360002_P01_FRONT-FIXED-GLASS-UNIT_CAD (Autodesk Fusion 360 design; units mm, degrees)
description: FRONT - FIXED GLASS UNIT | Cụm vách kính cố định | P01
part number: 360002
description: FRONT - FIXED GLASS - 4+4 LAMINATED | Tấm kính cố định 4+4 | P01
part number: 361003
description: FRONT - GLAZING U-PROFILE - BOHLE BO5201571 | Thanh U nhôm kẹp kính | P01
part number: 368004
description: FRONT - GLAZING U-SEAL - BOHLE BO5201735 | Gioăng chữ U silicone | P01
part number: 368002
description: FRONT - 180 MAGNETIC SEAL - HALF 1 OF 2 - HOLD | Gioăng nam châm 180° phía vách (chờ chọn) | P01
part number: 368003
Autodesk Fusion 360 part; units mm, degrees
sketch "OUTLINE - FIXED GLASS (SKELETON PENTAGON + BITE ON 4 EDGES)" plane through (0, 0, 0) normal (0, 1, 0) x (1, 0, 0) in component "361003 FRONT - FIXED GLASS - 4+4 LAMINATED"
  line L0 (218.9506, -98.5) -> (960.1034, -98.5)
  line L1 (960.1034, -98.5) -> (759.9166, -1525.9624)
  line L2 (759.9166, -1525.9624) -> (235.2521, -2131.5)
  line L3 (235.2521, -2131.5) -> (-66.1344, -2131.5)
  line L4 (-66.1344, -2131.5) -> (218.9506, -98.5)
  point P0 (-5000, 5000)
  dimension "d1397" = 5000
  dimension "d1398" = 5000
  dimension "d1399" = 5218.9506
  dimension "d1400" = 5960.1034
  dimension "d1401" = 5759.9166
  dimension "d1402" = 5235.2521
  dimension "d1403" = 4933.8656
  dimension "d1405" = 6525.9624
  constraint horizontal L0
  constraint horizontal L3
  measures "d1397" horizontal distance of origin P0
  measures "d1398" vertical distance of origin P0
  measures "d1399" horizontal distance of L0.start P0
  measures "d1400" horizontal distance of L0.end P0
  measures "d1401" horizontal distance of L1.end P0
  measures "d1402" horizontal distance of L2.end P0
  measures "d1403" horizontal distance of L3.end P0
  measures "d1405" vertical distance of L1.end P0
extrude "EXTRUDE - FIXED GLASS 8.76" add sketch "OUTLINE - FIXED GLASS (SKELETON PENTAGON + BITE ON 4 EDGES)" along normal blind 8.76 from surface at -703.38 makes body 1 in component "361003 FRONT - FIXED GLASS - 4+4 LAMINATED"
sketch "BAND - U-PROFILE OUTER (4 EDGES, MITRED)" plane through (0, 0, 0) normal (0, 1, 0) x (1, 0, 0) in component "368004 FRONT - GLAZING U-PROFILE - BOHLE BO5201571"
  line L0 (217.338, -110) -> (946.8781, -110)
  line L1 (946.8781, -110) -> (749, -1521)
  line L2 (749, -1521) -> (230, -2120)
  line L3 (230, -2120) -> (-64.5218, -2120)
  line L4 (-64.5218, -2120) -> (-66.6252, -2135)
  line L5 (-66.6252, -2135) -> (236.8506, -2135)
  line L6 (236.8506, -2135) -> (763.2391, -1527.4726)
  line L7 (763.2391, -1527.4726) -> (964.1285, -95)
  line L8 (964.1285, -95) -> (219.4414, -95)
  line L9 (219.4414, -95) -> (217.338, -110)
  point P0 (-5000, 5000)
  dimension "d1410" = 5000
  dimension "d1411" = 5000
  dimension "d1412" = 5217.338
  dimension "d1413" = 5946.8781
  dimension "d1414" = 5749
  dimension "d1415" = 5230
  dimension "d1416" = 4935.4782
  dimension "d1417" = 4933.3748
  dimension "d1418" = 5236.8506
  dimension "d1419" = 5763.2391
  dimension "d1420" = 5964.1285
  dimension "d1421" = 5219.4414
  dimension "d1422" = 5110
  dimension "d1423" = 6521
  dimension "d1424" = 7120
  dimension "d1426" = 6527.4726
  constraint horizontal L0
  constraint horizontal L3
  constraint horizontal L5
  constraint horizontal L8
  measures "d1410" horizontal distance of origin P0
  measures "d1411" vertical distance of origin P0
  measures "d1412" horizontal distance of L0.start P0
  measures "d1413" horizontal distance of L0.end P0
  measures "d1414" horizontal distance of L1.end P0
  measures "d1415" horizontal distance of L2.end P0
  measures "d1416" horizontal distance of L3.end P0
  measures "d1417" horizontal distance of L4.end P0
  measures "d1418" horizontal distance of L5.end P0
  measures "d1419" horizontal distance of L6.end P0
  measures "d1420" horizontal distance of L7.end P0
  measures "d1421" horizontal distance of L8.end P0
  measures "d1422" vertical distance of L0.start P0
  measures "d1423" vertical distance of L1.end P0
  measures "d1424" vertical distance of L2.end P0
  measures "d1426" vertical distance of L6.end P0
extrude "EXTRUDE - U-PROFILE BAR" add sketch "BAND - U-PROFILE OUTER (4 EDGES, MITRED)" along normal blind 15 from surface at -706.5 separate body makes body 2 in component "368004 FRONT - GLAZING U-PROFILE - BOHLE BO5201571"
sketch "BAND - U-PROFILE CHANNEL" plane through (0, 0, 0) normal (0, 1, 0) x (1, 0, 0) in component "368004 FRONT - GLAZING U-PROFILE - BOHLE BO5201571"
  line L0 (217.338, -110) -> (946.8781, -110)
  line L1 (946.8781, -110) -> (749, -1521)
  line L2 (749, -1521) -> (230, -2120)
  line L3 (230, -2120) -> (-64.5218, -2120)
  line L4 (-64.5218, -2120) -> (-66.4149, -2133.5)
  line L5 (-66.4149, -2133.5) -> (236.1655, -2133.5)
  line L6 (236.1655, -2133.5) -> (761.8152, -1526.8254)
  line L7 (761.8152, -1526.8254) -> (962.4034, -96.5)
  line L8 (962.4034, -96.5) -> (219.2311, -96.5)
  line L9 (219.2311, -96.5) -> (217.338, -110)
  point P0 (-5000, 5000)
  dimension "d1431" = 5000
  dimension "d1432" = 5000
  dimension "d1433" = 5217.338
  dimension "d1434" = 5946.8781
  dimension "d1435" = 5749
  dimension "d1436" = 5230
  dimension "d1437" = 4935.4782
  dimension "d1438" = 4933.5851
  dimension "d1439" = 5236.1655
  dimension "d1440" = 5761.8152
  dimension "d1441" = 5962.4034
  dimension "d1442" = 5219.2311
  dimension "d1443" = 5110
  dimension "d1444" = 6521
  dimension "d1445" = 7120
  dimension "d1447" = 6526.8254
  constraint horizontal L0
  constraint horizontal L3
  constraint horizontal L5
  constraint horizontal L8
  measures "d1431" horizontal distance of origin P0
  measures "d1432" vertical distance of origin P0
  measures "d1433" horizontal distance of L0.start P0
  measures "d1434" horizontal distance of L0.end P0
  measures "d1435" horizontal distance of L1.end P0
  measures "d1436" horizontal distance of L2.end P0
  measures "d1437" horizontal distance of L3.end P0
  measures "d1438" horizontal distance of L4.end P0
  measures "d1439" horizontal distance of L5.end P0
  measures "d1440" horizontal distance of L6.end P0
  measures "d1441" horizontal distance of L7.end P0
  measures "d1442" horizontal distance of L8.end P0
  measures "d1443" vertical distance of L0.start P0
  measures "d1444" vertical distance of L1.end P0
  measures "d1445" vertical distance of L2.end P0
  measures "d1447" vertical distance of L6.end P0
extrude "CUT - U-PROFILE CHANNEL 12 X 13.5" cut sketch "BAND - U-PROFILE CHANNEL" along normal blind 12 from surface at -705 bodies 2 in component "368004 FRONT - GLAZING U-PROFILE - BOHLE BO5201571"
sketch "HOLES - BOTTOM CHANNEL SCREWS TO THE SILL (4)" plane through (0, 0, 0) normal (0, 0, 1) x (1, 0, 0) in component "368004 FRONT - GLAZING U-PROFILE - BOHLE BO5201571"
  circle A0 centre (269.4414, -699) radius 1.7
  circle A1 centre (484.3371, -699) radius 1.7
  circle A2 centre (699.2328, -699) radius 1.7
  circle A3 centre (905, -699) radius 1.7
  point P0 (-5000, -5000)
  dimension "d1452" = 5000
  dimension "d1453" = 5000
  dimension "d1454" = 5269.4414
  dimension "d1456" = 3.4
  dimension "d1457" = 5484.3371
  dimension "d1459" = 3.4
  dimension "d1460" = 5699.2328
  dimension "d1462" = 3.4
  dimension "d1463" = 5905
  dimension "d1465" = 3.4
  measures "d1452" horizontal distance of origin P0
  measures "d1453" vertical distance of origin P0
  measures "d1454" horizontal distance of P0 A0.centre
  measures "d1456" diameter of A0
  measures "d1457" horizontal distance of P0 A1.centre
  measures "d1459" diameter of A1
  measures "d1460" horizontal distance of P0 A2.centre
  measures "d1462" diameter of A2
  measures "d1463" horizontal distance of P0 A3.centre
  measures "d1465" diameter of A3
extrude "CUT - BOTTOM CHANNEL SCREW HOLES" cut sketch "HOLES - BOTTOM CHANNEL SCREWS TO THE SILL (4)" along normal blind 3.5 from surface at 94 bodies 2 in component "368004 FRONT - GLAZING U-PROFILE - BOHLE BO5201571"
sketch "BAND - U-SEAL OUTER" plane through (0, 0, 0) normal (0, 1, 0) x (1, 0, 0) in component "368002 FRONT - GLAZING U-SEAL - BOHLE BO5201735"
  line L0 (217.338, -110) -> (946.8781, -110)
  line L1 (946.8781, -110) -> (749, -1521)
  line L2 (749, -1521) -> (230, -2120)
  line L3 (230, -2120) -> (-64.5218, -2120)
  line L4 (-64.5218, -2120) -> (-66.4149, -2133.5)
  line L5 (-66.4149, -2133.5) -> (236.1655, -2133.5)
  line L6 (236.1655, -2133.5) -> (761.8152, -1526.8254)
  line L7 (761.8152, -1526.8254) -> (962.4034, -96.5)
  line L8 (962.4034, -96.5) -> (219.2311, -96.5)
  line L9 (219.2311, -96.5) -> (217.338, -110)
  point P0 (-5000, 5000)
  dimension "d1469" = 5000
  dimension "d1470" = 5000
  dimension "d1471" = 5217.338
  dimension "d1472" = 5946.8781
  dimension "d1473" = 5749
  dimension "d1474" = 5230
  dimension "d1475" = 4935.4782
  dimension "d1476" = 4933.5851
  dimension "d1477" = 5236.1655
  dimension "d1478" = 5761.8152
  dimension "d1479" = 5962.4034
  dimension "d1480" = 5219.2311
  dimension "d1481" = 5110
  dimension "d1482" = 6521
  dimension "d1483" = 7120
  dimension "d1485" = 6526.8254
  constraint horizontal L0
  constraint horizontal L3
  constraint horizontal L5
  constraint horizontal L8
  measures "d1469" horizontal distance of origin P0
  measures "d1470" vertical distance of origin P0
  measures "d1471" horizontal distance of L0.start P0
  measures "d1472" horizontal distance of L0.end P0
  measures "d1473" horizontal distance of L1.end P0
  measures "d1474" horizontal distance of L2.end P0
  measures "d1475" horizontal distance of L3.end P0
  measures "d1476" horizontal distance of L4.end P0
  measures "d1477" horizontal distance of L5.end P0
  measures "d1478" horizontal distance of L6.end P0
  measures "d1479" horizontal distance of L7.end P0
  measures "d1480" horizontal distance of L8.end P0
  measures "d1481" vertical distance of L0.start P0
  measures "d1482" vertical distance of L1.end P0
  measures "d1483" vertical distance of L2.end P0
  measures "d1485" vertical distance of L6.end P0
extrude "EXTRUDE - U-SEAL" add sketch "BAND - U-SEAL OUTER" along normal blind 12 from surface at -705 separate body makes body 3 in component "368002 FRONT - GLAZING U-SEAL - BOHLE BO5201735"
sketch "BAND - U-SEAL GLASS SLOT" plane through (0, 0, 0) normal (0, 1, 0) x (1, 0, 0) in component "368002 FRONT - GLAZING U-SEAL - BOHLE BO5201735"
  line L0 (217.338, -110) -> (946.8781, -110)
  line L1 (946.8781, -110) -> (749, -1521)
  line L2 (749, -1521) -> (230, -2120)
  line L3 (230, -2120) -> (-64.5218, -2120)
  line L4 (-64.5218, -2120) -> (-66.1344, -2131.5)
  line L5 (-66.1344, -2131.5) -> (235.2521, -2131.5)
  line L6 (235.2521, -2131.5) -> (759.9166, -1525.9624)
  line L7 (759.9166, -1525.9624) -> (960.1034, -98.5)
  line L8 (960.1034, -98.5) -> (218.9506, -98.5)
  line L9 (218.9506, -98.5) -> (217.338, -110)
  point P0 (-5000, 5000)
  dimension "d1490" = 5000
  dimension "d1491" = 5000
  dimension "d1492" = 5217.338
  dimension "d1493" = 5946.8781
  dimension "d1494" = 5749
  dimension "d1495" = 5230
  dimension "d1496" = 4935.4782
  dimension "d1497" = 4933.8656
  dimension "d1498" = 5235.2521
  dimension "d1499" = 5759.9166
  dimension "d1500" = 5960.1034
  dimension "d1501" = 5218.9506
  dimension "d1502" = 5110
  dimension "d1503" = 6521
  dimension "d1504" = 7120
  dimension "d1506" = 6525.9624
  constraint horizontal L0
  constraint horizontal L3
  constraint horizontal L5
  constraint horizontal L8
  measures "d1490" horizontal distance of origin P0
  measures "d1491" vertical distance of origin P0
  measures "d1492" horizontal distance of L0.start P0
  measures "d1493" horizontal distance of L0.end P0
  measures "d1494" horizontal distance of L1.end P0
  measures "d1495" horizontal distance of L2.end P0
  measures "d1496" horizontal distance of L3.end P0
  measures "d1497" horizontal distance of L4.end P0
  measures "d1498" horizontal distance of L5.end P0
  measures "d1499" horizontal distance of L6.end P0
  measures "d1500" horizontal distance of L7.end P0
  measures "d1501" horizontal distance of L8.end P0
  measures "d1502" vertical distance of L0.start P0
  measures "d1503" vertical distance of L1.end P0
  measures "d1504" vertical distance of L2.end P0
  measures "d1506" vertical distance of L6.end P0
extrude "CUT - U-SEAL GLASS SLOT" cut sketch "BAND - U-SEAL GLASS SLOT" along normal blind 8.76 from surface at -703.38 bodies 3 in component "368002 FRONT - GLAZING U-SEAL - BOHLE BO5201735"
sketch "OUTLINE - 180 SEAL SPACE ON THE FREE EDGE" plane through (0, 0, 0) normal (0, 1, 0) x (1, 0, 0) in component "368003 FRONT - 180 MAGNETIC SEAL - HALF 1 OF 2 - HOLD"
  line L0 (217.338, -110) -> (-64.5218, -2120)
  line L1 (-64.5218, -2120) -> (-66.5413, -2120)
  line L2 (-66.5413, -2120) -> (215.3184, -110)
  line L3 (215.3184, -110) -> (217.338, -110)
  point P0 (-5000, 5000)
  dimension "d1511" = 5000
  dimension "d1512" = 5000
  dimension "d1513" = 5217.338
  dimension "d1514" = 4935.4782
  dimension "d1515" = 4933.4587
  dimension "d1516" = 5215.3184
  dimension "d1517" = 7120
  dimension "d1518" = 5110
  constraint horizontal L1
  constraint horizontal L3
  measures "d1511" horizontal distance of origin P0
  measures "d1512" vertical distance of origin P0
  measures "d1513" horizontal distance of L0.start P0
  measures "d1514" horizontal distance of L0.end P0
  measures "d1515" horizontal distance of L1.end P0
  measures "d1516" horizontal distance of L2.end P0
  measures "d1517" vertical distance of L0.end P0
  measures "d1518" vertical distance of L2.end P0
extrude "EXTRUDE - 180 SEAL SPACE" add sketch "OUTLINE - 180 SEAL SPACE ON THE FREE EDGE" along normal blind 11.76 from surface at -704.88 separate body makes body 4 in component "368003 FRONT - 180 MAGNETIC SEAL - HALF 1 OF 2 - HOLD"
component "361003 FRONT - FIXED GLASS - 4+4 LAMINATED" placed x (1, 0, 0) y (0, 1, 0) z (0, 0, 1) at (0, 0, 0)
component "368004 FRONT - GLAZING U-PROFILE - BOHLE BO5201571" placed x (1, 0, 0) y (0, 1, 0) z (0, 0, 1) at (0, 0, 0)
component "368002 FRONT - GLAZING U-SEAL - BOHLE BO5201735" placed x (1, 0, 0) y (0, 1, 0) z (0, 0, 1) at (0, 0, 0)
component "368003 FRONT - 180 MAGNETIC SEAL - HALF 1 OF 2 - HOLD" placed x (1, 0, 0) y (0, 1, 0) z (0, 0, 1) at (0, 0, 0)
equation "pod_w = 2500 mm" comment "SKELETON P04 DECIDED: D-01; conventions s4 (X = +-1250)"
equation "pod_d = 1700 mm" comment "SKELETON P04 DECIDED: D-01; conventions s4 (Y = +-850)"
equation "pod_h = 2400 mm" comment "SKELETON P04 DECIDED: D-21 (room floor to roof skin top)"
equation "glide_h = 10 mm" comment "SKELETON P04 ASSUMPTION: layout study inputs.py glide_h"
equation "band_h = 100 mm" comment "SKELETON P04 SOURCE: layout study B1 list B-BAND 100x40; inputs.py base_h"
equation "band_t = 40 mm" comment "SKELETON P04 SOURCE: layout study B1 list B-BAND 100x40"
equation "skin_t = 3 mm" comment "SKELETON P04 DECIDED: ACP skin, walls and ceiling (D-16; PM ruling 2026-10-31 on outer_t)"
equation "bond_t = 3 mm" comment "SKELETON P04 DECIDED: bond line between the ACP and the frame (PM ruling 2026-10-31 on outer_t)"
equation "frame_t = 40 mm" comment "SKELETON P04 DECIDED: aluminium frame tube depth, walls and ceiling (PM ruling 2026-10-31 on outer_t)"
equation "outer_t = skin_t + bond_t + frame_t" comment "SKELETON P04 DECIDED: PM ruling 2026-10-31: ACP 3 + bond line 3 + frame 40, walls and ceiling (was 43)"
equation "cav_gap = 4 mm" comment "SKELETON P04 DECIDED: D-16, D-42: the gap between the outer panel and the lining cassette in the wall and ceiling stack"
equation "cass_t = 34 mm" comment "SKELETON P04 SOURCE: layout study B1 final list L-CASS 34 (tray + 25 gap + felt 9)"
equation "stack_t = outer_t + cav_gap + cass_t" comment "SKELETON P04 CALCULATION: D-16, D-42 stack, walls and ceiling: outer panel + cavity gap + cassette (PM ruling 2026-10-31 on outer_t)"
equation "wall_depth = 1495 mm" comment "SKELETON P04 DECIDED: PM ruling pass C: side walls start at the decor back plate (Y -645), as v1 (1496)"
equation "lin_gap = 4 mm" comment "SKELETON P04 ASSUMPTION: PM ruling pass C: gap above the upper side linings so they stay floating (= the 4 mm stack gap)"
equation "seam_gap = 2.26 mm" comment "SKELETON P04 DECIDED: PM ruling 2026-10-31 (Mechanical Checker F-001, F-005): the Joints Engineer's 2.26 mm at all nine site seam types, set by a metal stop (1.5 stop washer + 0.76 rivnut head; joints register section 2.8)"
equation "mat_t = 3 mm" comment "SKELETON P04 DECIDED: D-72, PM ruling 2026-10-31 (from BASE): the 3 mm floor mat under the floor ply"
equation "floor_t = 9 mm" comment "SKELETON P04 DECIDED: PM ruling 2026-10-31: 9 mm floor panels (was 15, layout study B1 list), on the mat"
equation "thresh_h = 13 mm" comment "SKELETON P04 DECIDED: PM ruling 2026-10-31: 13 mm, a US-accessible threshold (D-18 had 20); the kick strip keeps its kick_gap above it"
equation "thresh_d = 60 mm" comment "SKELETON P04 SOURCE: layout study B1 list B-THRESH 1176 x 60 x 20"
equation "decor_d = 205 mm" comment "SKELETON P04 SOURCE: v1 geometry per the PM ruling on D-39 (as v1; the drawings win): v1 decor-frame drawing frames 191 (left) and 197 (right) deep plus ACP and back plate = the v1 STEP shell, Y -850 to -645 = 205. D-39 and the B1 list say 230-235 (v1 BOM); see BUILD-RECORD-P02"
equation "dl_w = 278 mm" comment "SKELETON P04 SOURCE: B1 list F-DL 278 (v1 BOM DL)"
equation "dr_w = 1016 mm" comment "SKELETON P04 SOURCE: B1 list F-DR 1016 (v1 STEP solid 78)"
equation "dt_w = 1697 mm" comment "SKELETON P04 SOURCE: B1 list F-DT 1697 (v1 BOM DT)"
equation "dt_h = 280 mm" comment "SKELETON P04 SOURCE: B1 list F-DT 280"
equation "door_w = 1176 mm" comment "SKELETON P04 DECIDED: D-46"
equation "door_h = 2011 mm" comment "SKELETON P04 SOURCE: B1 list F-GLASS-DOOR 2011; v1 STEP solid 238"
equation "glass_t = 8.76 mm" comment "SKELETON P04 DECIDED: D-46 (4+4 laminate)"
equation "glass_y = 699 mm" comment "SKELETON P04 SOURCE: v1 STEP solid 238 centre Y = -699 (layout study data)"
equation "kick_d = 20 mm" comment "SKELETON P04 ASSUMPTION: kick strip envelope depth (D-40 gives the height only)"
equation "kick_gap = 7 mm" comment "SKELETON P04 SOURCE: FRONT door unit: 7 mm running gap between the threshold and the kick strip for the drop seal (Mechanical Checker F-002 on P03)"
equation "fr_dz = 17 mm" comment "SKELETON P04 CALCULATION: v1 front top 2417 (v2 frame) - pod_h 2400"
equation "door_xl = 289 mm" comment "SKELETON P04 SOURCE: V1-FRONT-FACETS: door left edge X -961 = -1250 + 289"
equation "door_xbr = 1464 mm" comment "SKELETON P04 SOURCE: V1-FRONT-FACETS: door bottom-right X 214"
equation "door_xtr = 1182 mm" comment "SKELETON P04 SOURCE: V1-FRONT-FACETS: door top-right X -68"
equation "door_zb = 122 mm - fr_dz" comment "SKELETON P04 SOURCE: V1-FRONT-FACETS: door bottom Z 122"
equation "door_zt = 2133 mm - fr_dz" comment "SKELETON P04 SOURCE: V1-FRONT-FACETS: door top Z 2133"
equation "glass_gap = 4 mm" comment "SKELETON P04 DECIDED: PM ruling 2026-10-31 on Mechanical Checker F-014: the fixed glass's free edge runs parallel to the door's slanted edge, 4.0 mm away (FRONT's glass in PR #28 is the reference)"
equation "fix_xbr = 302 mm" comment "SKELETON P04 SOURCE: V1-FRONT-FACETS: fixed glass bottom-right X 948 = 1250 - 302"
equation "fix_xk = 501 mm" comment "SKELETON P04 SOURCE: V1-FRONT-FACETS: fixed glass knee X 749 = 1250 - 501"
equation "fix_zk = 1538 mm - fr_dz" comment "SKELETON P04 SOURCE: V1-FRONT-FACETS: fixed glass knee Z 1538"
equation "fix_xtr = 1480 mm" comment "SKELETON P04 SOURCE: V1-FRONT-FACETS: fixed glass top-right X 230 = -1250 + 1480"
equation "fix_zb = 119 mm - fr_dz" comment "SKELETON P04 SOURCE: V1-FRONT-FACETS: fixed glass bottom Z 119"
equation "fix_zt = 2136 mm - fr_dz" comment "SKELETON P04 SOURCE: V1-FRONT-FACETS: fixed glass top Z 2136"
equation "dt_zb = 2137 mm - fr_dz" comment "SKELETON P04 SOURCE: V1-FRONT-FACETS: DT and DR edge above the glass Z 2137"
equation "ch_zlo = 2217 mm - fr_dz" comment "SKELETON P04 SOURCE: V1-FRONT-FACETS: top chamfer front edge Z 2217 at Y -848"
equation "ch_yb = 672 mm" comment "SKELETON P04 SOURCE: V1-FRONT-FACETS: top chamfer back edge Y -672"
equation "dl_x2 = 92 mm" comment "SKELETON P04 SOURCE: V1-FRONT-FACETS: DL facet knee X -1158 = -1250 + 92"
equation "dl_y2 = 752 mm" comment "SKELETON P04 SOURCE: V1-FRONT-FACETS: DL facet knee Y -752"
equation "dl_x3 = 271 mm" comment "SKELETON P04 SOURCE: V1-FRONT-FACETS: DL front corner X -979"
equation "dl_y3 = 844 mm" comment "SKELETON P04 SOURCE: V1-FRONT-FACETS: DL front corner Y -844"
equation "dl_y1 = 670 mm" comment "SKELETON P04 SOURCE: V1-FRONT-FACETS: DL outer facet start Y -670"
equation "dl_zo = 2414 mm - fr_dz" comment "SKELETON P04 SOURCE: V1-FRONT-FACETS: DL top at the outer corner Z 2414"
equation "dt_x2 = 281 mm" comment "SKELETON P04 SOURCE: V1-FRONT-FACETS: DT lower facet left X -969 = -1250 + 281"
equation "dt_y2 = 767 mm" comment "SKELETON P04 SOURCE: V1-FRONT-FACETS: DT lower facet left Y -767"
equation "dt_y3 = 753 mm" comment "SKELETON P04 SOURCE: V1-FRONT-FACETS: DT lower facet outer Y -753 at X -1154"
equation "dr_xc = 198 mm" comment "SKELETON P04 SOURCE: V1-FRONT-FACETS: DR corner facet front X 1052 = 1250 - 198"
equation "dt_xr = 1699 mm" comment "SKELETON P04 SOURCE: V1-FRONT-FACETS: DT/DR joint at the top, X 449 = -1250 + 1699 (PM ruling pass C)"
equation "dr_yc = 672 mm" comment "SKELETON P04 SOURCE: V1-FRONT-FACETS: DR corner facet back Y -672"
equation "fix_xbl = door_xbr + ( door_zb - fix_zb ) * ( door_xbr - door_xtr ) / ( door_zt - door_zb ) + glass_gap * sqrt(( door_xbr - door_xtr ) * ( door_xbr - door_xtr ) + ( door_zt - door_zb ) * ( door_zt - door_zb )) / ( door_zt - door_zb )" comment "SKELETON P04 CALCULATION: F-014: fixed glass bottom-left, on the line glass_gap from the door's slanted edge (was v1's 1468)"
equation "fix_xtl = door_xbr + ( door_zb - fix_zt ) * ( door_xbr - door_xtr ) / ( door_zt - door_zb ) + glass_gap * sqrt(( door_xbr - door_xtr ) * ( door_xbr - door_xtr ) + ( door_zt - door_zb ) * ( door_zt - door_zb )) / ( door_zt - door_zb )" comment "SKELETON P04 CALCULATION: F-014: fixed glass top-left, on the same line (was v1's 1184)"
equation "floor_top = mat_t + floor_t" comment "SKELETON P04 CALCULATION: D-72: the floor top, Z 12 (mat 3 + ply 9); the threshold stands thresh_h above the room floor"
equation "wall_z0 = glide_h + band_h" comment "SKELETON P04 CALCULATION: base band top: glides + band"
equation "panel_z0 = wall_z0 + seam_gap" comment "SKELETON P04 CALCULATION: walls stand one seam_gap above the band top (joints register 2.8, IF-01)"
equation "wall_h = pod_h - wall_z0" comment "SKELETON P04 CALCULATION: 2290 = layout study v2_model wall_h"
equation "side_h = ( wall_h - 2 * seam_gap ) / 2" comment "SKELETON P04 CALCULATION: D-23: 2 sheets per side wall; the gap on the band and the horizontal seam (joints register 2.8)"
equation "side_l = wall_depth - seam_gap" comment "SKELETON P04 CALCULATION: side panel length along Y: the seam_gap at the decor's back plate (joints register 2.8, IF-07)"
equation "back_oh = pod_h - outer_t - seam_gap - panel_z0" comment "SKELETON P04 CALCULATION: PM ruling 2026-10-31 (pass D, F-004): the back outer frames run up to the ceiling frame (pod_h - outer_t), less the seam_gap under it, closing the slot at the back top edge"
equation "back_ph = ( back_oh - seam_gap ) / 2" comment "SKELETON P04 CALCULATION: D-23: 4 sheets on the back, two equal rows with one seam_gap between them (joints register 2.8); the lower back linings match the lower row, as on the side walls"
equation "half_pw = ( pod_w - 2 * outer_t - 3 * seam_gap ) / 2" comment "SKELETON P04 CALCULATION: SKIN width of each back and ceiling panel: two skins and three seam_gap seams between the side frames (F-001, joints register 2.8)"
equation "close_gap = 5.5 mm" comment "SKELETON P04 DECIDED: PM ruling 2026-10-31 (joints register, F-011/F-012): frame gap at the closing seams B1-B2, B3-B4 and C1-C2, which have no hard stop (slotted holes, thicker gasket)"
equation "half_fw = ( pod_w - 2 * outer_t - 2 * seam_gap - close_gap ) / 2" comment "SKELETON P04 CALCULATION: FRAME width of each back and ceiling panel: the skins overhang their frames by half_pw - half_fw at the closing seam (PM ruling 2026-10-31)"
equation "inner_w = pod_w - 2 * stack_t" comment "SKELETON P04 CALCULATION: inside width between the side linings"
equation "bolt_edge_inset = 220 mm" comment "SKELETON P04 DECIDED: PM ruling 2026-10-31: on every bolted edge the end bolts sit this far in from each panel end (the FRAME end, where the bolts go), the rest evenly spaced"
equation "spigot_inset = 100 mm" comment "SKELETON P04 DECIDED: PM ruling 2026-10-31: locating spigots this far in from each panel end (round hole at one end, slot at the other)"
equation "base_bolt_edge = bolt_edge_inset" comment "SKELETON P04 DECIDED: J-BASE-01 wall to band: the edge rule (kept by this name for parts already linked)"
equation "n_base_bolt = 4" comment "SKELETON P04 DECIDED: PM ruling 2026-10-31, J-BASE-01: bolts per panel along the band, evenly spaced"
equation "base_spigot_inset = spigot_inset" comment "SKELETON P04 DECIDED: J-BASE-01: the spigot rule (kept by this name for parts already linked)"
equation "base_side_y0 = pod_d / 2 - wall_depth + seam_gap" comment "SKELETON P04 CALCULATION: J-BASE-01: side bolt lines start at the side panel's front end (first bolt base_bolt_edge further on)"
equation "side_base_pitch = ( side_l - 2 * base_bolt_edge ) / ( n_base_bolt - 1 )" comment "SKELETON P04 CALCULATION: J-BASE-01 bolt pitch along a side panel"
equation "base_back_x0 = pod_w / 2 - outer_t - seam_gap" comment "SKELETON P04 CALCULATION: J-BASE-01: back bolt lines start at each back FRAME's outer end, X -/+ this (first bolt base_bolt_edge further in)"
equation "back_base_pitch = ( half_fw - 2 * base_bolt_edge ) / ( n_base_bolt - 1 )" comment "SKELETON P04 DECIDED: PM ruling 2026-10-31 (Reviewer 5 P2 on #58): J-BASE-01 pitch along a back panel, measured on the FRAME (half_fw), where the bolts go; 'panel end' means the frame end"
equation "ceil_bolt_z = pod_h - outer_t + frame_t / 2" comment "SKELETON P04 DECIDED: PM ruling 2026-10-31, J-CEIL-01 wall to ceiling: the bolt line on the ceiling frame's centre (Z 2374)"
equation "n_ceil_side_bolt = 4" comment "SKELETON P04 DECIDED: PM ruling 2026-10-31, J-CEIL-01: bolts along each side wall top"
equation "n_ceil_back_bolt = 4" comment "SKELETON P04 DECIDED: PM ruling 2026-10-31, J-CEIL-01: bolts along each back panel top, like the base (pitch about 253, every edge 350 or less; joints register: 82 bolts in all)"
equation "ceil_side_y0 = pod_d / 2 - wall_depth" comment "SKELETON P04 DECIDED: PM ruling 2026-10-31 (joints register): J-CEIL-01 side bolt lines start at Y -645, measured along the ceiling (first bolt bolt_edge_inset further on)"
equation "ceil_side_pitch = ( wall_depth - 2 * bolt_edge_inset ) / ( n_ceil_side_bolt - 1 )" comment "SKELETON P04 DECIDED: PM ruling 2026-10-31 (joints register): J-CEIL-01 pitch along a side wall top, over the ceiling's length (was over the side panel's)"
equation "ceil_back_x0 = pod_w / 2 - outer_t - seam_gap" comment "SKELETON P04 DECIDED: PM ruling 2026-10-31 (joints register): J-CEIL-01 back bolt lines start at each back frame's outer end, X -/+ this"
equation "ceil_back_pitch = ( half_fw - 2 * bolt_edge_inset ) / ( n_ceil_back_bolt - 1 )" comment "SKELETON P04 DECIDED: PM ruling 2026-10-31 (joints register): J-CEIL-01 pitch along a back panel top, on the frame (half_fw)"
equation "sk_ref = 5000 mm" comment "ASSUMPTION: sketch reference point offset: every sketch corner is dimensioned from a point at -sk_ref on both plane axes, so no dimension changes side when a corner crosses a pod centre line in an edit"
equation "fg_vis_zb = wall_z0" comment "CALCULATION: visible bottom of the fixed pane = the base band top (DL and DR stop there too, PM ruling 2026-10-31)"
equation "fg_vis_zt = dt_zb" comment "CALCULATION: visible top of the fixed pane = DT's underside"
equation "fg_gap = glass_gap" comment "CALCULATION: = the skeleton's glass_gap: the pane's free edge runs parallel to the door's latch edge, 4 mm off (PM ruling 2026-10-31; the skeleton's fix_xbl and fix_xtl follow the same rule since its update #58)"
equation "gu_prof_w = 15 mm" comment "SOURCE: Bohle BO5201571 aluminium U-profile 15 x 15 x 1.5 (hardware selection C5)"
equation "gu_prof_d = 15 mm" comment "SOURCE: as gu_prof_w"
equation "gu_prof_t = 1.5 mm" comment "SOURCE: as gu_prof_w"
equation "gu_w = gu_prof_w - 2 * gu_prof_t" comment "CALCULATION: inner width of the U-profile = the U-seal's outer width"
equation "gu_base = 2 mm" comment "ASSUMPTION: U-seal base under the glass edge; HOLD for Bohle's BO5201735 section drawing"
equation "gu_in_d = gu_prof_d - gu_prof_t" comment "CALCULATION: inner depth of the U-profile"
equation "fg_bite = gu_in_d - gu_base" comment "CALCULATION: glass cover in the hidden channels, 11.5 (PM ruling 2026-10-31); HOLD for the glass supplier's minimum"
equation "fg_r_len = sqrt(( fix_xbr - fix_xk ) * ( fix_xbr - fix_xk ) + ( fix_zk - fix_zb ) * ( fix_zk - fix_zb ))" comment "CALCULATION: length of the skeleton's right edge (bottom-right corner to the knee)"
equation "fg_rnx = ( fix_zk - fix_zb ) / fg_r_len" comment "CALCULATION: right edge outward normal, X"
equation "fg_rnz = ( fix_xk - fix_xbr ) / fg_r_len" comment "CALCULATION: right edge outward normal, Z"
equation "fg_rc = fg_rnx * ( pod_w / 2 - fix_xbr ) + fg_rnz * fix_zb" comment "CALCULATION: right edge line constant"
equation "fg_d_len = sqrt(( pod_w - fix_xtr - fix_xk ) * ( pod_w - fix_xtr - fix_xk ) + ( dt_zb - fix_zk ) * ( dt_zb - fix_zk ))" comment "CALCULATION: length of DR's diagonal inner edge (knee to DT's underside at X -pod_w/2 + fix_xtr)"
equation "fg_dnx = ( dt_zb - fix_zk ) / fg_d_len" comment "CALCULATION: diagonal outward normal, X"
equation "fg_dnz = ( pod_w - fix_xtr - fix_xk ) / fg_d_len" comment "CALCULATION: diagonal outward normal, Z"
equation "fg_dc = fg_dnx * ( pod_w / 2 - fix_xk ) + fg_dnz * fix_zk" comment "CALCULATION: diagonal line constant"
equation "fg_det = fg_rnx * fg_dnz - fg_rnz * fg_dnx" comment "CALCULATION: for the knee corner"
equation "fg_l_len = sqrt(( door_xbr - door_xtr ) * ( door_xbr - door_xtr ) + ( door_zt - door_zb ) * ( door_zt - door_zb ))" comment "CALCULATION: length of the door's latch edge"
equation "fg_lnx = ( door_zt - door_zb ) / fg_l_len" comment "CALCULATION: door latch edge normal toward the pane, X"
equation "fg_lnz = ( door_xbr - door_xtr ) / fg_l_len" comment "CALCULATION: door latch edge normal toward the pane, Z"
equation "fg_lc = fg_lnx * ( -pod_w / 2 + door_xbr ) + fg_lnz * door_zb" comment "CALCULATION: door latch edge line constant"
equation "gs_end = 50 mm" comment "SOURCE: PM ruling 2026-11-01 (BASE's sill): channel screws 50 from each end"
equation "gs_hole = 3.4 mm" comment "SOURCE: ISO 273 medium clearance hole for M3 (screw ISO 10642 M3 x 8, A2)"
equation "gs_csk = 7 mm" comment "CALCULATION: 90 deg countersink on the channel's inside face, over the ISO 10642 M3 head (6.72 max); the head stands about 0.4 proud of the 1.5 base and the U-seal's base covers it"
equation "gs_xl = ( ( fg_lc + fg_gap - fg_lnz * ( ( fg_vis_zb - gu_prof_d ) ) ) / fg_lnx )" comment "CALCULATION: left end of the bottom channel's underside (the pane's free edge)"
equation "gs_xr = ( ( fg_rc + gu_prof_d - fg_rnz * ( ( fg_vis_zb - gu_prof_d ) ) ) / fg_rnx )" comment "CALCULATION: right end of the bottom channel's underside, where it is mitred into the right-edge channel"
equation "base_fr1_x = 915 mm" comment "SOURCE: joints register (#127): BASE's front band inline joint FR1 at X 915; no sill rivnut on it (PM ruling 2026-11-01)"
equation "gs_x4 = base_fr1_x - 10 mm" comment "CONFIRMED: the last channel screw at X 905, clear of FR1's end; BASE moved the sill's last rivnut to match and kept the first three (PM ruling 2026-11-01); 59 from the channel's right end"
equation "gs_p = ( gs_xr - gs_xl - 2 * gs_end ) / 3" comment "CALCULATION: pitch of the first 3 channel screws (X 269.4, 484.3, 699.2, as BASE's sill rivnuts); 300 or less (PM ruling)"
equation "d1397 = sk_ref"
equation "d1398 = sk_ref"
equation "d1399 = ( ( ( fg_lc + fg_gap - fg_lnz * ( ( fg_vis_zb - fg_bite ) ) ) / fg_lnx ) ) + sk_ref"
equation "d1400 = ( ( ( fg_rc + fg_bite - fg_rnz * ( ( fg_vis_zb - fg_bite ) ) ) / fg_rnx ) ) + sk_ref"
equation "d1401 = ( ( ( ( fg_rc + fg_bite ) * fg_dnz - ( fg_dc + fg_bite ) * fg_rnz ) / fg_det ) ) + sk_ref"
equation "d1402 = ( ( ( fg_dc + fg_bite - fg_dnz * ( ( fg_vis_zt + fg_bite ) ) ) / fg_dnx ) ) + sk_ref"
equation "d1403 = ( ( ( fg_lc + fg_gap - fg_lnz * ( ( fg_vis_zt + fg_bite ) ) ) / fg_lnx ) ) + sk_ref"
equation "d1404 = ( ( fg_vis_zb - fg_bite ) ) + sk_ref"
equation "d1405 = ( ( ( fg_rnx * ( fg_dc + fg_bite ) - fg_dnx * ( fg_rc + fg_bite ) ) / fg_det ) ) + sk_ref"
equation "d1406 = ( ( fg_vis_zt + fg_bite ) ) + sk_ref"
equation "d1407 = ( -glass_y - glass_t / 2 ) * ( 1 )"
equation "d1408 = ( -glass_y + glass_t / 2 ) - ( -glass_y - glass_t / 2 )"
equation "d1410 = sk_ref"
equation "d1411 = sk_ref"
equation "d1412 = ( ( ( fg_lc + fg_gap - fg_lnz * ( ( fg_vis_zb - 0 mm ) ) ) / fg_lnx ) ) + sk_ref"
equation "d1413 = ( ( ( fg_rc + 0 mm - fg_rnz * ( ( fg_vis_zb - 0 mm ) ) ) / fg_rnx ) ) + sk_ref"
equation "d1414 = ( ( ( ( fg_rc + 0 mm ) * fg_dnz - ( fg_dc + 0 mm ) * fg_rnz ) / fg_det ) ) + sk_ref"
equation "d1415 = ( ( ( fg_dc + 0 mm - fg_dnz * ( ( fg_vis_zt + 0 mm ) ) ) / fg_dnx ) ) + sk_ref"
equation "d1416 = ( ( ( fg_lc + fg_gap - fg_lnz * ( ( fg_vis_zt + 0 mm ) ) ) / fg_lnx ) ) + sk_ref"
equation "d1417 = ( ( ( fg_lc + fg_gap - fg_lnz * ( ( fg_vis_zt + gu_prof_d ) ) ) / fg_lnx ) ) + sk_ref"
equation "d1418 = ( ( ( fg_dc + gu_prof_d - fg_dnz * ( ( fg_vis_zt + gu_prof_d ) ) ) / fg_dnx ) ) + sk_ref"
equation "d1419 = ( ( ( ( fg_rc + gu_prof_d ) * fg_dnz - ( fg_dc + gu_prof_d ) * fg_rnz ) / fg_det ) ) + sk_ref"
equation "d1420 = ( ( ( fg_rc + gu_prof_d - fg_rnz * ( ( fg_vis_zb - gu_prof_d ) ) ) / fg_rnx ) ) + sk_ref"
equation "d1421 = ( ( ( fg_lc + fg_gap - fg_lnz * ( ( fg_vis_zb - gu_prof_d ) ) ) / fg_lnx ) ) + sk_ref"
equation "d1422 = ( ( fg_vis_zb - 0 mm ) ) + sk_ref"
equation "d1423 = ( ( ( fg_rnx * ( fg_dc + 0 mm ) - fg_dnx * ( fg_rc + 0 mm ) ) / fg_det ) ) + sk_ref"
equation "d1424 = ( ( fg_vis_zt + 0 mm ) ) + sk_ref"
equation "d1425 = ( ( fg_vis_zt + gu_prof_d ) ) + sk_ref"
equation "d1426 = ( ( ( fg_rnx * ( fg_dc + gu_prof_d ) - fg_dnx * ( fg_rc + gu_prof_d ) ) / fg_det ) ) + sk_ref"
equation "d1427 = ( ( fg_vis_zb - gu_prof_d ) ) + sk_ref"
equation "d1428 = ( -glass_y - gu_prof_w / 2 ) * ( 1 )"
equation "d1429 = ( -glass_y + gu_prof_w / 2 ) - ( -glass_y - gu_prof_w / 2 )"
equation "d1431 = sk_ref"
equation "d1432 = sk_ref"
equation "d1433 = ( ( ( fg_lc + fg_gap - fg_lnz * ( ( fg_vis_zb - 0 mm ) ) ) / fg_lnx ) ) + sk_ref"
equation "d1434 = ( ( ( fg_rc + 0 mm - fg_rnz * ( ( fg_vis_zb - 0 mm ) ) ) / fg_rnx ) ) + sk_ref"
equation "d1435 = ( ( ( ( fg_rc + 0 mm ) * fg_dnz - ( fg_dc + 0 mm ) * fg_rnz ) / fg_det ) ) + sk_ref"
equation "d1436 = ( ( ( fg_dc + 0 mm - fg_dnz * ( ( fg_vis_zt + 0 mm ) ) ) / fg_dnx ) ) + sk_ref"
equation "d1437 = ( ( ( fg_lc + fg_gap - fg_lnz * ( ( fg_vis_zt + 0 mm ) ) ) / fg_lnx ) ) + sk_ref"
equation "d1438 = ( ( ( fg_lc + fg_gap - fg_lnz * ( ( fg_vis_zt + gu_in_d ) ) ) / fg_lnx ) ) + sk_ref"
equation "d1439 = ( ( ( fg_dc + gu_in_d - fg_dnz * ( ( fg_vis_zt + gu_in_d ) ) ) / fg_dnx ) ) + sk_ref"
equation "d1440 = ( ( ( ( fg_rc + gu_in_d ) * fg_dnz - ( fg_dc + gu_in_d ) * fg_rnz ) / fg_det ) ) + sk_ref"
equation "d1441 = ( ( ( fg_rc + gu_in_d - fg_rnz * ( ( fg_vis_zb - gu_in_d ) ) ) / fg_rnx ) ) + sk_ref"
equation "d1442 = ( ( ( fg_lc + fg_gap - fg_lnz * ( ( fg_vis_zb - gu_in_d ) ) ) / fg_lnx ) ) + sk_ref"
equation "d1443 = ( ( fg_vis_zb - 0 mm ) ) + sk_ref"
equation "d1444 = ( ( ( fg_rnx * ( fg_dc + 0 mm ) - fg_dnx * ( fg_rc + 0 mm ) ) / fg_det ) ) + sk_ref"
equation "d1445 = ( ( fg_vis_zt + 0 mm ) ) + sk_ref"
equation "d1446 = ( ( fg_vis_zt + gu_in_d ) ) + sk_ref"
equation "d1447 = ( ( ( fg_rnx * ( fg_dc + gu_in_d ) - fg_dnx * ( fg_rc + gu_in_d ) ) / fg_det ) ) + sk_ref"
equation "d1448 = ( ( fg_vis_zb - gu_in_d ) ) + sk_ref"
equation "d1449 = ( -glass_y - gu_w / 2 ) * ( 1 )"
equation "d1450 = ( -glass_y + gu_w / 2 ) - ( -glass_y - gu_w / 2 )"
equation "d1452 = sk_ref"
equation "d1453 = sk_ref"
equation "d1454 = ( gs_xl + gs_end + 0 * gs_p ) + sk_ref"
equation "d1455 = ( -glass_y ) + sk_ref"
equation "d1456 = gs_hole"
equation "d1457 = ( gs_xl + gs_end + 1 * gs_p ) + sk_ref"
equation "d1458 = ( -glass_y ) + sk_ref"
equation "d1459 = gs_hole"
equation "d1460 = ( gs_xl + gs_end + 2 * gs_p ) + sk_ref"
equation "d1461 = ( -glass_y ) + sk_ref"
equation "d1462 = gs_hole"
equation "d1463 = ( gs_x4 ) + sk_ref"
equation "d1464 = ( -glass_y ) + sk_ref"
equation "d1465 = gs_hole"
equation "d1466 = ( ( fg_vis_zb - gu_prof_d ) - 1 mm ) * ( 1 )"
equation "d1467 = ( ( fg_vis_zb - gu_prof_d ) + gu_prof_t + 1 mm ) - ( ( fg_vis_zb - gu_prof_d ) - 1 mm )"
equation "d1469 = sk_ref"
equation "d1470 = sk_ref"
equation "d1471 = ( ( ( fg_lc + fg_gap - fg_lnz * ( ( fg_vis_zb - 0 mm ) ) ) / fg_lnx ) ) + sk_ref"
equation "d1472 = ( ( ( fg_rc + 0 mm - fg_rnz * ( ( fg_vis_zb - 0 mm ) ) ) / fg_rnx ) ) + sk_ref"
equation "d1473 = ( ( ( ( fg_rc + 0 mm ) * fg_dnz - ( fg_dc + 0 mm ) * fg_rnz ) / fg_det ) ) + sk_ref"
equation "d1474 = ( ( ( fg_dc + 0 mm - fg_dnz * ( ( fg_vis_zt + 0 mm ) ) ) / fg_dnx ) ) + sk_ref"
equation "d1475 = ( ( ( fg_lc + fg_gap - fg_lnz * ( ( fg_vis_zt + 0 mm ) ) ) / fg_lnx ) ) + sk_ref"
equation "d1476 = ( ( ( fg_lc + fg_gap - fg_lnz * ( ( fg_vis_zt + gu_in_d ) ) ) / fg_lnx ) ) + sk_ref"
equation "d1477 = ( ( ( fg_dc + gu_in_d - fg_dnz * ( ( fg_vis_zt + gu_in_d ) ) ) / fg_dnx ) ) + sk_ref"
equation "d1478 = ( ( ( ( fg_rc + gu_in_d ) * fg_dnz - ( fg_dc + gu_in_d ) * fg_rnz ) / fg_det ) ) + sk_ref"
equation "d1479 = ( ( ( fg_rc + gu_in_d - fg_rnz * ( ( fg_vis_zb - gu_in_d ) ) ) / fg_rnx ) ) + sk_ref"
equation "d1480 = ( ( ( fg_lc + fg_gap - fg_lnz * ( ( fg_vis_zb - gu_in_d ) ) ) / fg_lnx ) ) + sk_ref"
equation "d1481 = ( ( fg_vis_zb - 0 mm ) ) + sk_ref"
equation "d1482 = ( ( ( fg_rnx * ( fg_dc + 0 mm ) - fg_dnx * ( fg_rc + 0 mm ) ) / fg_det ) ) + sk_ref"
equation "d1483 = ( ( fg_vis_zt + 0 mm ) ) + sk_ref"
equation "d1484 = ( ( fg_vis_zt + gu_in_d ) ) + sk_ref"
equation "d1485 = ( ( ( fg_rnx * ( fg_dc + gu_in_d ) - fg_dnx * ( fg_rc + gu_in_d ) ) / fg_det ) ) + sk_ref"
equation "d1486 = ( ( fg_vis_zb - gu_in_d ) ) + sk_ref"
equation "d1487 = ( -glass_y - gu_w / 2 ) * ( 1 )"
equation "d1488 = ( -glass_y + gu_w / 2 ) - ( -glass_y - gu_w / 2 )"
equation "d1490 = sk_ref"
equation "d1491 = sk_ref"
equation "d1492 = ( ( ( fg_lc + fg_gap - fg_lnz * ( ( fg_vis_zb - 0 mm ) ) ) / fg_lnx ) ) + sk_ref"
equation "d1493 = ( ( ( fg_rc + 0 mm - fg_rnz * ( ( fg_vis_zb - 0 mm ) ) ) / fg_rnx ) ) + sk_ref"
equation "d1494 = ( ( ( ( fg_rc + 0 mm ) * fg_dnz - ( fg_dc + 0 mm ) * fg_rnz ) / fg_det ) ) + sk_ref"
equation "d1495 = ( ( ( fg_dc + 0 mm - fg_dnz * ( ( fg_vis_zt + 0 mm ) ) ) / fg_dnx ) ) + sk_ref"
equation "d1496 = ( ( ( fg_lc + fg_gap - fg_lnz * ( ( fg_vis_zt + 0 mm ) ) ) / fg_lnx ) ) + sk_ref"
equation "d1497 = ( ( ( fg_lc + fg_gap - fg_lnz * ( ( fg_vis_zt + fg_bite ) ) ) / fg_lnx ) ) + sk_ref"
equation "d1498 = ( ( ( fg_dc + fg_bite - fg_dnz * ( ( fg_vis_zt + fg_bite ) ) ) / fg_dnx ) ) + sk_ref"
equation "d1499 = ( ( ( ( fg_rc + fg_bite ) * fg_dnz - ( fg_dc + fg_bite ) * fg_rnz ) / fg_det ) ) + sk_ref"
equation "d1500 = ( ( ( fg_rc + fg_bite - fg_rnz * ( ( fg_vis_zb - fg_bite ) ) ) / fg_rnx ) ) + sk_ref"
equation "d1501 = ( ( ( fg_lc + fg_gap - fg_lnz * ( ( fg_vis_zb - fg_bite ) ) ) / fg_lnx ) ) + sk_ref"
equation "d1502 = ( ( fg_vis_zb - 0 mm ) ) + sk_ref"
equation "d1503 = ( ( ( fg_rnx * ( fg_dc + 0 mm ) - fg_dnx * ( fg_rc + 0 mm ) ) / fg_det ) ) + sk_ref"
equation "d1504 = ( ( fg_vis_zt + 0 mm ) ) + sk_ref"
equation "d1505 = ( ( fg_vis_zt + fg_bite ) ) + sk_ref"
equation "d1506 = ( ( ( fg_rnx * ( fg_dc + fg_bite ) - fg_dnx * ( fg_rc + fg_bite ) ) / fg_det ) ) + sk_ref"
equation "d1507 = ( ( fg_vis_zb - fg_bite ) ) + sk_ref"
equation "d1508 = ( -glass_y - glass_t / 2 ) * ( 1 )"
equation "d1509 = ( -glass_y + glass_t / 2 ) - ( -glass_y - glass_t / 2 )"
equation "d1511 = sk_ref"
equation "d1512 = sk_ref"
equation "d1513 = ( ( ( fg_lc + fg_gap - fg_lnz * ( ( fg_vis_zb - 0 mm ) ) ) / fg_lnx ) ) + sk_ref"
equation "d1514 = ( ( ( fg_lc + fg_gap - fg_lnz * ( ( fg_vis_zt + 0 mm ) ) ) / fg_lnx ) ) + sk_ref"
equation "d1515 = ( ( ( fg_lc + fg_gap / 2 - fg_lnz * ( ( fg_vis_zt + 0 mm ) ) ) / fg_lnx ) ) + sk_ref"
equation "d1516 = ( ( ( fg_lc + fg_gap / 2 - fg_lnz * ( ( fg_vis_zb - 0 mm ) ) ) / fg_lnx ) ) + sk_ref"
equation "d1517 = ( ( fg_vis_zt + 0 mm ) ) + sk_ref"
equation "d1518 = ( ( fg_vis_zb - 0 mm ) ) + sk_ref"
equation "d1519 = ( -glass_y - glass_t / 2 - 1.5 mm ) * ( 1 )"
equation "d1520 = ( -glass_y + glass_t / 2 + 1.5 mm ) - ( -glass_y - glass_t / 2 - 1.5 mm )"
named bodies: "FIXED GLASS 4+4", "GLAZING U-PROFILE (4 PIECES, MITRED)", "GLAZING U-SEAL (4 PIECES)", "180 MAGNETIC SEAL - FIXED PANE HALF (HOLD PRODUCT)"
